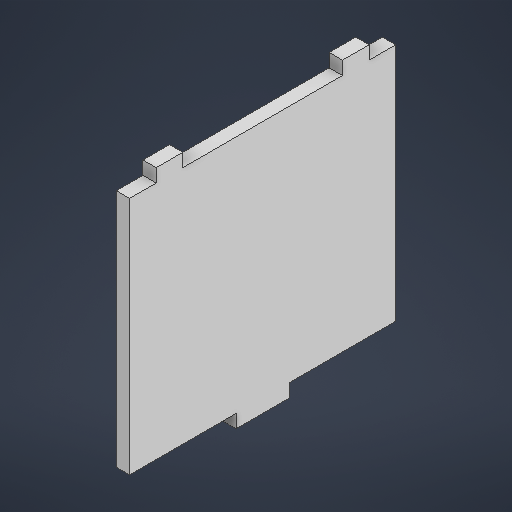
# Autodesk Inventor part: Pared1
Saved by Autodesk Inventor 2025.2 (Build 292293000, 293)
## iProperties
Created: 2025-06-03
Part Number: Pared1
Material: Genérico
Document SubType Name: Modeling
Designer: Niko
Density: 1 g/cm^3
Appearance: Valor por defecto
Author: Niko
Autodesk Inventor part; units mm, degrees
ref_plane "YZ Plane" through (0, 0, 0) normal (1, 0, 0) x (0, 1, 0)
ref_plane "XZ Plane" through (0, 0, 0) normal (0, 1, 0) x (-1, 0, 0)
ref_plane "XY Plane" through (0, 0, 0) normal (0, 0, 1) x (1, 0, 0)
sketch "Boceto1" plane through (0, 0, 0) normal (1, 0, 0) x (0, 1, 0)
  line L0 (0, 50) -> (45, 50)
  line L1 (45, 50) -> (-45, 50)
  line L2 (-50, 10) -> (-50, -10)
  line L3 (-45, -50) -> (45, -50)
  line L4 (45, 50) -> (45, 40)
  line L5 (45, 40) -> (50, 40)
  line L6 (45, -50) -> (45, -40)
  line L7 (45, -40) -> (50, -40)
  line L8 (50, -40) -> (50, -30)
  line L9 (50, -30) -> (45, -30)
  line L10 (45, -30) -> (45, 30)
  line L11 (45, 30) -> (50, 30)
  line L12 (-45, 50) -> (-45, 10)
  line L13 (-45, 10) -> (-50, 10)
  line L14 (-45, -50) -> (-45, -10)
  line L15 (-45, -10) -> (-50, -10)
  line L16 (50, -40) -> (50, -30)
  line L17 (50, 30) -> (50, 40)
  point P0 (0, 0)
  constraints: 36 end point, 11 perpendicular, 6 point on line, 3 parallel, 1 horizontal, 1 vertical
extrude "Extrusión1" add sketch "Boceto1" along normal blind 5
